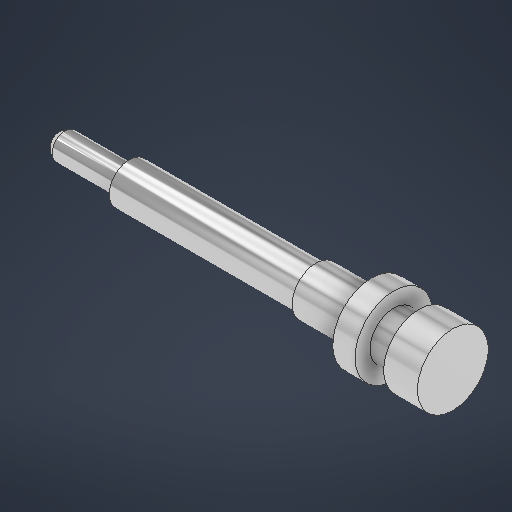
# Autodesk Inventor part: s1101mfp1022
Saved by Autodesk Inventor 2027.1 (Build 311270010, 270A)
## iProperties
Created: 2026-10-31
Part Number: s1101mfp1022
Material: Generic
Document SubType Name: Modeling
Designer: User
Density: 1 g/cm^3
Appearance: Chrome - Polished
Author: User
Autodesk Inventor part; units mm, degrees
ref_plane "YZ Plane" through (0, 0, 0) normal (1, 0, 0) x (0, 1, 0)
ref_plane "XZ Plane" through (0, 0, 0) normal (0, 1, 0) x (-1, 0, 0)
ref_plane "XY Plane" through (0, 0, 0) normal (0, 0, 1) x (1, 0, 0)
sketch "Sketch1" plane through (0, 0, 0) normal (0, 0, 1) x (1, 0, 0)
  line L0 (-8.128, 24.9961) -> (-8.128, 27.7901)
  line L1 (-8.128, 27.7901) -> (-6.35, 28.9331)
  line L2 (-6.35, 28.9331) -> (13.0048, 28.9331)
  line L3 (13.0048, 28.9331) -> (13.0048, 31.0921)
  line L4 (13.0048, 31.0921) -> (69.2404, 31.0921)
  line L5 (69.2404, 31.0921) -> (69.2404, 32.1843)
  line L6 (69.2404, 32.1843) -> (86.0044, 32.1843)
  line L7 (86.0044, 32.1843) -> (86.0044, 36.6801)
  line L8 (86.0044, 36.6801) -> (92.71, 36.6801)
  line L9 (92.71, 36.6801) -> (92.71, 32.1843)
  line L10 (92.71, 32.1843) -> (100.33, 32.1843)
  line L11 (100.33, 32.1843) -> (100.33, 35.6641)
  line L12 (100.33, 35.6641) -> (110.49, 35.6641)
  line L13 (110.49, 35.6641) -> (110.49, 24.9961)
  line L14 (110.49, 24.9961) -> (-8.128, 24.9961)
  line L15 (-12.7, 24.9961) -> (114.3, 24.9961)
  constraints: 32 end point
revolve "Revolution1" add sketch "Sketch1" angle 360 about axis through (-12.7, 24.9961, 0) along (1, 0, 0)
body "Solid1"
